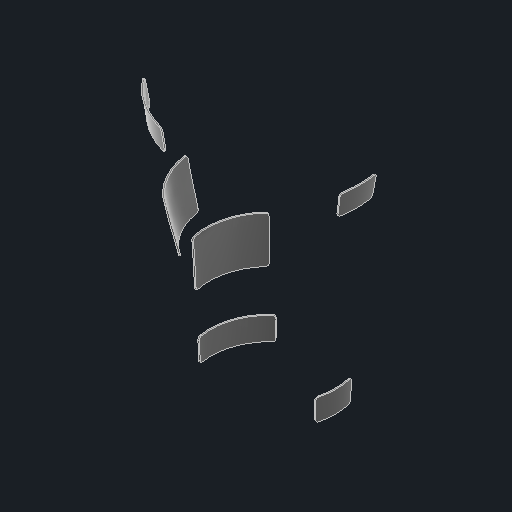
# Autodesk Inventor part: velcro
Saved by Autodesk Inventor 2026.2 (Build 302298010, 298A)
## iProperties
Created: 2026-04-16
Part Number: velcro
Material: Velcro Hook 88 / Loop 1000 (woven nylon, D12-4)
Document SubType Name: Modeling
Designer: user
Density: 0.109 g/cm^3
Appearance: Smooth - Black
Description: Copy of velcro, geometry unchanged. Material: Velcro Hook 88 / Loop 1000 - density from areal mass (TDS001-1), strength = dynamic shear 8.3 N/cm2, E/nu Nylon 6/6 (closest).
Mass: 2.13433 g
Surface Area: 280.537 cm^2
Volume: 19.581 cm^3
Author: user
Autodesk Inventor part; units mm, degrees
(part 1 of 2)
sketch "Sketch1" plane through (0, 0, 0) normal (0, 0, 1) x (1, 0, 0)
  line L0 (-180.6859, 44.2752) -> (-125.6859, 44.2752)
  arc A0 (-180.6859, 44.2752) -> (-180.6859, 21.2752) centre (-180.6859, 32.7752) ccw
  line L1 (-125.6859, 21.2752) -> (-180.6859, 21.2752)
  line L2 (-230.6859, -15.7248) -> (-125.6859, -15.7248)
  arc A1 (-230.6859, -15.7248) -> (-230.6859, -38.7248) centre (-230.6859, -27.2248) ccw
  line L3 (-125.6859, -38.7248) -> (-230.6859, -38.7248)
  line L4 (-125.6859, -38.7248) -> (-230.6859, -38.7248)
  arc A2 (-230.6859, -15.7248) -> (-230.6859, -38.7248) centre (-230.6859, -27.2248) ccw
  line L5 (-125.6859, -15.7248) -> (-125.6859, -38.7248)
  line L6 (-130.6859, 21.2752) -> (-180.6859, 21.2752)
  arc A3 (-180.6859, 44.2752) -> (-180.6859, 21.2752) centre (-180.6859, 32.7752) ccw
  line L7 (-242.1859, -27.2248) -> (-242.1859, 70.7547) construction
  line L8 (-125.6859, -27.2248) -> (-30.1859, -27.2248) construction
  line L9 (-30.1859, -27.2248) -> (-30.1859, 61.1167) construction
  line L10 (-15.419, 32.7752) -> (-30.1859, 32.7752) construction
  line L11 (-230.6859, -27.2248) -> (-230.6859, 28.0133) construction
  line L12 (-180.6859, 57.1317) -> (-180.6859, 8.4187) construction
  line L13 (-158.7098, 32.7752) -> (-202.6621, 32.7752) construction
  line L14 (-158.7098, 41.392) -> (-158.7098, 16.946) construction
  line L15 (-125.6859, 21.2752) -> (-125.6859, 44.2752)
  point P0 (0, 0)
  point P1 (-178.1859, -15.7248)
  dimension "d7" = 105
  dimension "d8" = 105
  dimension "d11" = 95.5
  dimension "d14" = 50
  dimension "d17" = 48.5
  constraints: 32 end point, 9 point on circle, 5 vertical, 4 centre point, 4 midpoint, 4 tangent, 3 horizontal, 3 point on line, 2 perpendicular, 1 coincident, 1 collinear
  measures "d7" distance of L2.start L5.start
  measures "d8" distance of L5.end L3.end
  measures "d11" distance of L8.start L8.end
  measures "d14" distance from line of L11 point (-180.686, 32.775)
  measures "d17" vertical distance of point (-178.186, -15.725) A0.centre
extrude "Extrusion1" [suppressed]
fillet "Fillet1" [suppressed]
ref_plane "Webbing_outer_face_X9.18" through (9.18, 0, 0) normal (1, 0, 0) x (0, 1, 0)
sketch "Velcro_v5" plane through (9.18, 0, 0) normal (1, 0, 0) x (0, 1, 0)
  line L0 (95.66, 344.45) -> (121.06, 344.45)
  line L1 (121.06, 344.45) -> (121.06, 416.45)
  line L2 (121.06, 416.45) -> (95.66, 416.45)
  line L3 (95.66, 416.45) -> (95.66, 344.45)
  line L4 (147.96, 340.5125) -> (198.76, 340.5125)
  line L5 (198.76, 340.5125) -> (198.76, 412.5125)
  line L6 (198.76, 412.5125) -> (147.96, 412.5125)
  line L7 (147.96, 412.5125) -> (147.96, 340.5125)
  line L8 (217.96, -556.485) -> (268.76, -556.485)
  line L9 (268.76, -556.485) -> (268.76, -484.485)
  line L10 (268.76, -484.485) -> (217.96, -484.485)
  line L11 (217.96, -484.485) -> (217.96, -556.485)
  line L12 (295.66, -604.3) -> (321.06, -604.3)
  line L13 (321.06, -604.3) -> (321.06, -532.3)
  line L14 (321.06, -532.3) -> (295.66, -532.3)
  line L15 (295.66, -532.3) -> (295.66, -604.3)
  line L16 (88.36, -60.14) -> (113.36, -60.14)
  line L17 (113.36, -60.14) -> (113.36, -20.14)
  line L18 (113.36, -20.14) -> (88.36, -20.14)
  line L19 (88.36, -20.14) -> (88.36, -60.14)
  line L20 (303.36, -60.14) -> (328.36, -60.14)
  line L21 (328.36, -60.14) -> (328.36, -20.14)
  line L22 (328.36, -20.14) -> (303.36, -20.14)
  line L23 (303.36, -20.14) -> (303.36, -60.14)
  constraints: 48 end point, 12 parallel, 6 horizontal, 6 perpendicular
extrude "Velcro_1.5mm" [suppressed]
ref_plane "Work Plane2" through (0, 0, 0) normal (0.7916281, 0, 0.6110032) x (0, 1, 0)
sketch "S7_vel_thigh_far" plane through (0, 0, 0) normal (0.7916281, 0, 0.6110032) x (0, 1, 0)
  spline S0 degree 4 poles (87.3, 89.6977) (87.4763, 89.7284) (87.829, 89.7897) (88.3579, 89.8816) (89.0633, 90.0041) (89.7686, 90.1263) (90.4739, 90.2483) (91.1793, 90.3702) (91.8847, 90.4919) (92.59, 90.6135) (93.2954, 90.7349) (94.0008, 90.8561) (94.7063, 90.9772) (95.4117, 91.0981) (96.1171, 91.2189) (96.8226, 91.3395) (97.528, 91.46) (98.2335, 91.5804) (98.939, 91.7006) (99.6445, 91.8207) (100.35, 91.9406) (101.0555, 92.0603) (101.7611, 92.1796) (102.4666, 92.2985) (103.1723, 92.4172) (103.8779, 92.5354) (104.5835, 92.6534) (105.2892, 92.7711) (105.9949, 92.8885) (106.7006, 93.0056) (107.4064, 93.1224) (108.1121, 93.2389) (108.8179, 93.3552) (109.5237, 93.4712) (110.2295, 93.5869) (110.9353, 93.7024) (111.6412, 93.8177) (112.1706, 93.904) (112.5235, 93.9614) (112.7, 93.9901) knots 0 0 0 0 0 0.027778 0.055556 0.083333 0.111111 0.138889 0.166667 0.194444 0.222222 0.25 0.277778 0.305556 0.333333 0.361111 0.388889 0.416667 0.444444 0.472222 0.5 0.527778 0.555556 0.583333 0.611111 0.638889 0.666667 0.694444 0.722222 0.75 0.777778 0.805556 0.833333 0.861111 0.888889 0.916667 0.944444 0.972222 1 1 1 1 1
  line L0 (112.7, 93.9901) -> (112.7, 95.4901)
  spline S1 degree 4 poles (112.7, 95.4901) (112.5235, 95.4614) (112.1706, 95.404) (111.6412, 95.3177) (110.9353, 95.2024) (110.2295, 95.0869) (109.5237, 94.9712) (108.8179, 94.8552) (108.1121, 94.7389) (107.4064, 94.6224) (106.7006, 94.5056) (105.9949, 94.3885) (105.2892, 94.2711) (104.5835, 94.1534) (103.8779, 94.0354) (103.1723, 93.9172) (102.4666, 93.7986) (101.7611, 93.6796) (101.0555, 93.5603) (100.35, 93.4406) (99.6445, 93.3207) (98.939, 93.2006) (98.2335, 93.0804) (97.528, 92.96) (96.8226, 92.8395) (96.1171, 92.7189) (95.4117, 92.5981) (94.7063, 92.4772) (94.0008, 92.3561) (93.2954, 92.2349) (92.59, 92.1135) (91.8847, 91.9919) (91.1793, 91.8702) (90.4739, 91.7483) (89.7686, 91.6263) (89.0633, 91.5041) (88.3579, 91.3816) (87.829, 91.2897) (87.4763, 91.2284) (87.3, 91.1977) knots 0 0 0 0 0 0.027778 0.055556 0.083333 0.111111 0.138889 0.166667 0.194444 0.222222 0.25 0.277778 0.305556 0.333333 0.361111 0.388889 0.416667 0.444444 0.472222 0.5 0.527778 0.555556 0.583333 0.611111 0.638889 0.666667 0.694444 0.722222 0.75 0.777778 0.805556 0.833333 0.861111 0.888889 0.916667 0.944444 0.972222 1 1 1 1 1
  line L1 (87.3, 91.1977) -> (87.3, 89.6977)
  line L2 (81.8572, 0) -> (118.1369, 0) projected
  point P0 (90.1222, 90.1875)
  point P1 (92.9444, 90.6745)
  point P2 (95.7667, 91.1589)
  point P3 (98.5889, 91.6409)
  point P4 (101.4111, 92.1204)
  point P5 (104.2333, 92.5948)
  point P6 (107.0556, 93.0643)
  point P7 (109.8778, 93.5292)
  point P8 (109.8778, 95.0292)
  point P9 (107.0556, 94.5643)
  point P10 (104.2333, 94.0948)
  point P11 (101.4111, 93.6204)
  point P12 (98.5889, 93.1409)
  point P13 (95.7667, 92.6589)
  point P14 (92.9444, 92.1745)
  point P15 (90.1222, 91.6875)
  constraints: 4 end point, 20 other
revolve "Velcro_closure_thigh_far" [suppressed]
ref_plane "Work Plane3" through (0, 0, 0) normal (0.5346339, 0, 0.8450838) x (0, 1, 0)
sketch "S7_vel_thigh_near" plane through (0, 0, 0) normal (0.5346339, 0, 0.8450838) x (0, 1, 0)
  spline S0 degree 4 poles (9.6, 73.5055) (9.7877, 73.538) (10.1629, 73.6035) (10.7256, 73.7037) (11.4755, 73.8411) (12.2251, 73.9824) (12.9744, 74.1274) (13.7233, 74.276) (14.472, 74.4282) (15.2203, 74.5837) (15.9683, 74.7423) (16.716, 74.9038) (17.4634, 75.0681) (18.2105, 75.2351) (18.9574, 75.4046) (19.704, 75.5765) (20.4504, 75.7507) (21.1966, 75.9269) (21.9425, 76.1051) (22.6883, 76.2851) (23.4338, 76.4668) (24.1792, 76.65) (24.9245, 76.8345) (25.6696, 77.0203) (26.4145, 77.2072) (27.1594, 77.395) (27.9042, 77.5836) (28.6488, 77.7729) (29.3935, 77.9627) (30.138, 78.1528) (30.8826, 78.3433) (31.6271, 78.5338) (32.3717, 78.7242) (33.1163, 78.9145) (33.8609, 79.1045) (34.6055, 79.294) (35.3503, 79.4829) (36.0951, 79.671) (36.84, 79.8583) (37.5851, 80.0444) (38.3302, 80.2295) (39.0756, 80.4132) (39.821, 80.5955) (40.5667, 80.7763) (41.3126, 80.9552) (42.0587, 81.1322) (42.805, 81.307) (43.5515, 81.4797) (44.2983, 81.6501) (45.0453, 81.8182) (45.7926, 81.9839) (46.5402, 82.1468) (47.2881, 82.3066) (48.0363, 82.463) (48.7848, 82.6158) (49.5337, 82.7654) (50.2827, 82.9126) (51.032, 83.0582) (51.7812, 83.203) (52.5305, 83.3477) (53.2799, 83.4923) (54.0292, 83.6367) (54.7785, 83.7806) (55.5279, 83.9241) (56.2774, 84.067) (57.0269, 84.2095) (57.7764, 84.3516) (58.526, 84.4933) (59.2756, 84.6348) (59.8378, 84.7407) (60.2126, 84.8112) (60.4, 84.8465) knots 0 0 0 0 0 0.014706 0.029412 0.044118 0.058824 0.073529 0.088235 0.102941 0.117647 0.132353 0.147059 0.161765 0.176471 0.191176 0.205882 0.220588 0.235294 0.25 0.264706 0.279412 0.294118 0.308824 0.323529 0.338235 0.352941 0.367647 0.382353 0.397059 0.411765 0.426471 0.441176 0.455882 0.470588 0.485294 0.5 0.514706 0.529412 0.544118 0.558824 0.573529 0.588235 0.602941 0.617647 0.632353 0.647059 0.661765 0.676471 0.691176 0.705882 0.720588 0.735294 0.75 0.764706 0.779412 0.794118 0.808824 0.823529 0.838235 0.852941 0.867647 0.882353 0.897059 0.911765 0.926471 0.941176 0.955882 0.970588 0.985294 1 1 1 1 1
  line L0 (60.4, 84.8465) -> (60.4, 86.3465)
  spline S1 degree 4 poles (60.4, 86.3465) (60.2126, 86.3112) (59.8378, 86.2407) (59.2756, 86.1348) (58.526, 85.9933) (57.7764, 85.8516) (57.0269, 85.7095) (56.2774, 85.567) (55.5279, 85.4241) (54.7785, 85.2806) (54.0292, 85.1367) (53.2799, 84.9923) (52.5305, 84.8477) (51.7812, 84.7031) (51.032, 84.5582) (50.2827, 84.4126) (49.5337, 84.2654) (48.7848, 84.1158) (48.0363, 83.963) (47.2881, 83.8066) (46.5402, 83.6468) (45.7926, 83.4839) (45.0453, 83.3182) (44.2983, 83.1501) (43.5515, 82.9797) (42.805, 82.807) (42.0587, 82.6322) (41.3126, 82.4552) (40.5667, 82.2763) (39.821, 82.0955) (39.0756, 81.9132) (38.3302, 81.7295) (37.5851, 81.5444) (36.84, 81.3583) (36.0951, 81.171) (35.3503, 80.9829) (34.6055, 80.794) (33.8609, 80.6045) (33.1163, 80.4145) (32.3717, 80.2242) (31.6271, 80.0338) (30.8826, 79.8433) (30.138, 79.6529) (29.3935, 79.4627) (28.6488, 79.2729) (27.9042, 79.0836) (27.1594, 78.895) (26.4145, 78.7072) (25.6696, 78.5203) (24.9245, 78.3345) (24.1792, 78.15) (23.4338, 77.9668) (22.6883, 77.7851) (21.9425, 77.6051) (21.1966, 77.4269) (20.4504, 77.2507) (19.704, 77.0765) (18.9574, 76.9046) (18.2105, 76.7351) (17.4634, 76.5681) (16.716, 76.4038) (15.9683, 76.2423) (15.2203, 76.0837) (14.472, 75.9282) (13.7233, 75.776) (12.9744, 75.6274) (12.2251, 75.4824) (11.4755, 75.3411) (10.7256, 75.2037) (10.1629, 75.1035) (9.7877, 75.038) (9.6, 75.0055) knots 0 0 0 0 0 0.014706 0.029412 0.044118 0.058824 0.073529 0.088235 0.102941 0.117647 0.132353 0.147059 0.161765 0.176471 0.191176 0.205882 0.220588 0.235294 0.25 0.264706 0.279412 0.294118 0.308824 0.323529 0.338235 0.352941 0.367647 0.382353 0.397059 0.411765 0.426471 0.441176 0.455882 0.470588 0.485294 0.5 0.514706 0.529412 0.544118 0.558824 0.573529 0.588235 0.602941 0.617647 0.632353 0.647059 0.661765 0.676471 0.691176 0.705882 0.720588 0.735294 0.75 0.764706 0.779412 0.794118 0.808824 0.823529 0.838235 0.852941 0.867647 0.882353 0.897059 0.911765 0.926471 0.941176 0.955882 0.970588 0.985294 1 1 1 1 1
  line L1 (9.6, 75.0055) -> (9.6, 73.5055)
  line L2 (-1.3086, 0) -> (71.2778, 0) projected
  point P0 (12.5882, 74.0529)
  point P1 (15.5765, 74.6595)
  point P2 (18.5647, 75.3157)
  point P3 (21.5529, 76.0122)
  point P4 (24.5412, 76.7397)
  point P5 (27.5294, 77.4888)
  point P6 (30.5176, 78.2499)
  point P7 (33.5059, 79.0139)
  point P8 (36.4941, 79.7712)
  point P9 (39.4824, 80.5126)
  point P10 (42.4706, 81.2285)
  point P11 (45.4588, 81.9096)
  point P12 (48.4471, 82.5466)
  point P13 (51.4353, 83.1361)
  point P14 (54.4235, 83.7124)
  point P15 (57.4118, 84.2824)
  point P16 (57.4118, 85.7824)
  point P17 (54.4235, 85.2124)
  point P18 (51.4353, 84.6361)
  point P19 (48.4471, 84.0466)
  point P20 (45.4588, 83.4096)
  point P21 (42.4706, 82.7285)
  point P22 (39.4824, 82.0126)
  point P23 (36.4941, 81.2712)
  point P24 (33.5059, 80.5139)
  point P25 (30.5176, 79.7499)
  point P26 (27.5294, 78.9888)
  point P27 (24.5412, 78.2397)
  point P28 (21.5529, 77.5122)
  point P29 (18.5647, 76.8157)
  point P30 (15.5765, 76.1595)
  point P31 (12.5882, 75.5529)
  constraints: 4 end point, 36 other
revolve "Velcro_closure_thigh_near" [suppressed]
ref_plane "Work Plane4" through (0, 0, 0) normal (-0.2561526, 0, 0.9666364) x (0, 1, 0)
sketch "S7_vel_shank_near" plane through (0, 0, 0) normal (-0.2561526, 0, 0.9666364) x (0, 1, 0)
  spline S0 degree 4 poles (-60.4, 68.8155) (-60.2132, 68.8227) (-59.8395, 68.8372) (-59.279, 68.859) (-58.5317, 68.8882) (-57.7844, 68.9177) (-57.0371, 68.9474) (-56.2898, 68.9773) (-55.5426, 69.0075) (-54.7953, 69.0379) (-54.048, 69.0686) (-53.3007, 69.0995) (-52.5535, 69.1307) (-51.8062, 69.1621) (-51.0589, 69.1938) (-50.3117, 69.2258) (-49.5644, 69.258) (-48.8172, 69.2906) (-48.07, 69.3234) (-47.3227, 69.3565) (-46.5755, 69.3899) (-45.8283, 69.4236) (-45.0811, 69.4576) (-44.3339, 69.4919) (-43.5867, 69.5265) (-42.8395, 69.5615) (-42.0923, 69.5967) (-41.3452, 69.6323) (-40.598, 69.6682) (-39.8508, 69.7045) (-39.1037, 69.7411) (-38.3565, 69.7781) (-37.6094, 69.8154) (-36.8623, 69.8531) (-36.1152, 69.8911) (-35.3681, 69.9295) (-34.621, 69.9682) (-33.8739, 70.0074) (-33.1268, 70.0469) (-32.3797, 70.0868) (-31.6327, 70.1271) (-30.8856, 70.1678) (-30.1386, 70.2089) (-29.3915, 70.2504) (-28.6445, 70.2923) (-27.8975, 70.3346) (-27.1505, 70.3774) (-26.4035, 70.4205) (-25.6566, 70.4641) (-24.9096, 70.5081) (-24.1626, 70.5526) (-23.4157, 70.5975) (-22.6688, 70.6429) (-21.9219, 70.6887) (-21.175, 70.7349) (-20.4281, 70.7817) (-19.6812, 70.8289) (-18.9344, 70.8765) (-18.1875, 70.9247) (-17.4407, 70.9733) (-16.6939, 71.0224) (-15.9471, 71.072) (-15.2003, 71.1221) (-14.4536, 71.1727) (-13.7068, 71.2237) (-12.9601, 71.2754) (-12.2134, 71.3275) (-11.4667, 71.3801) (-10.72, 71.4333) (-10.16, 71.4735) (-9.7867, 71.5006) (-9.6, 71.5141) knots 0 0 0 0 0 0.014706 0.029412 0.044118 0.058824 0.073529 0.088235 0.102941 0.117647 0.132353 0.147059 0.161765 0.176471 0.191176 0.205882 0.220588 0.235294 0.25 0.264706 0.279412 0.294118 0.308824 0.323529 0.338235 0.352941 0.367647 0.382353 0.397059 0.411765 0.426471 0.441176 0.455882 0.470588 0.485294 0.5 0.514706 0.529412 0.544118 0.558824 0.573529 0.588235 0.602941 0.617647 0.632353 0.647059 0.661765 0.676471 0.691176 0.705882 0.720588 0.735294 0.75 0.764706 0.779412 0.794118 0.808824 0.823529 0.838235 0.852941 0.867647 0.882353 0.897059 0.911765 0.926471 0.941176 0.955882 0.970588 0.985294 1 1 1 1 1
  line L0 (-9.6, 71.5141) -> (-9.6, 73.0141)
  spline S1 degree 4 poles (-9.6, 73.0141) (-9.7867, 73.0006) (-10.16, 72.9735) (-10.72, 72.9333) (-11.4667, 72.8801) (-12.2134, 72.8275) (-12.9601, 72.7754) (-13.7068, 72.7237) (-14.4536, 72.6727) (-15.2003, 72.6221) (-15.9471, 72.572) (-16.6939, 72.5224) (-17.4407, 72.4733) (-18.1875, 72.4247) (-18.9344, 72.3765) (-19.6812, 72.3289) (-20.4281, 72.2817) (-21.175, 72.2349) (-21.9219, 72.1887) (-22.6688, 72.1429) (-23.4157, 72.0975) (-24.1626, 72.0526) (-24.9096, 72.0081) (-25.6566, 71.9641) (-26.4035, 71.9205) (-27.1505, 71.8774) (-27.8975, 71.8346) (-28.6445, 71.7923) (-29.3915, 71.7504) (-30.1386, 71.7089) (-30.8856, 71.6678) (-31.6327, 71.6271) (-32.3797, 71.5868) (-33.1268, 71.5469) (-33.8739, 71.5074) (-34.621, 71.4682) (-35.3681, 71.4295) (-36.1152, 71.3911) (-36.8623, 71.3531) (-37.6094, 71.3154) (-38.3565, 71.2781) (-39.1037, 71.2411) (-39.8508, 71.2045) (-40.598, 71.1682) (-41.3452, 71.1323) (-42.0923, 71.0967) (-42.8395, 71.0615) (-43.5867, 71.0265) (-44.3339, 70.9919) (-45.0811, 70.9576) (-45.8283, 70.9236) (-46.5755, 70.8899) (-47.3227, 70.8565) (-48.07, 70.8234) (-48.8172, 70.7906) (-49.5644, 70.758) (-50.3117, 70.7258) (-51.0589, 70.6938) (-51.8062, 70.6621) (-52.5535, 70.6307) (-53.3007, 70.5995) (-54.048, 70.5686) (-54.7953, 70.5379) (-55.5426, 70.5075) (-56.2898, 70.4773) (-57.0371, 70.4474) (-57.7844, 70.4177) (-58.5317, 70.3882) (-59.279, 70.359) (-59.8395, 70.3372) (-60.2132, 70.3227) (-60.4, 70.3155) knots 0 0 0 0 0 0.014706 0.029412 0.044118 0.058824 0.073529 0.088235 0.102941 0.117647 0.132353 0.147059 0.161765 0.176471 0.191176 0.205882 0.220588 0.235294 0.25 0.264706 0.279412 0.294118 0.308824 0.323529 0.338235 0.352941 0.367647 0.382353 0.397059 0.411765 0.426471 0.441176 0.455882 0.470588 0.485294 0.5 0.514706 0.529412 0.544118 0.558824 0.573529 0.588235 0.602941 0.617647 0.632353 0.647059 0.661765 0.676471 0.691176 0.705882 0.720588 0.735294 0.75 0.764706 0.779412 0.794118 0.808824 0.823529 0.838235 0.852941 0.867647 0.882353 0.897059 0.911765 0.926471 0.941176 0.955882 0.970588 0.985294 1 1 1 1 1
  line L1 (-60.4, 70.3155) -> (-60.4, 68.8155)
  line L2 (-71.2749, 0) -> (1.2865, 0) projected
  point P0 (-57.4118, 68.9325)
  point P1 (-54.4235, 69.0532)
  point P2 (-51.4353, 69.1779)
  point P3 (-48.4471, 69.3068)
  point P4 (-45.4588, 69.4404)
  point P5 (-42.4706, 69.5789)
  point P6 (-39.4824, 69.7226)
  point P7 (-36.4941, 69.8718)
  point P8 (-33.5059, 70.0269)
  point P9 (-30.5176, 70.1881)
  point P10 (-27.5294, 70.3557)
  point P11 (-24.5412, 70.5301)
  point P12 (-21.5529, 70.7116)
  point P13 (-18.5647, 70.9004)
  point P14 (-15.5765, 71.0969)
  point P15 (-12.5882, 71.3014)
  point P16 (-12.5882, 72.8014)
  point P17 (-15.5765, 72.5969)
  point P18 (-18.5647, 72.4004)
  point P19 (-21.5529, 72.2116)
  point P20 (-24.5412, 72.0301)
  point P21 (-27.5294, 71.8557)
  point P22 (-30.5176, 71.6881)
  point P23 (-33.5059, 71.5269)
  point P24 (-36.4941, 71.3718)
  point P25 (-39.4824, 71.2226)
  point P26 (-42.4706, 71.0789)
  point P27 (-45.4588, 70.9404)
  point P28 (-48.4471, 70.8068)
  point P29 (-51.4353, 70.6779)
  point P30 (-54.4235, 70.5532)
  point P31 (-57.4118, 70.4325)
  constraints: 4 end point, 36 other
revolve "Velcro_closure_shank_near" [suppressed]
ref_plane "Work Plane5" through (0, 0, 0) normal (-0.3395989, 0, 0.9405703) x (0, 1, 0)
sketch "S7_vel_shank_far" plane through (0, 0, 0) normal (-0.3395989, 0, 0.9405703) x (0, 1, 0)
  spline S0 degree 4 poles (-112.7, 67.0412) (-112.5236, 67.0472) (-112.1708, 67.0594) (-111.6417, 67.0776) (-110.9361, 67.1017) (-110.2306, 67.1258) (-109.5251, 67.1497) (-108.8195, 67.1736) (-108.114, 67.1974) (-107.4084, 67.221) (-106.7029, 67.2446) (-105.9973, 67.2682) (-105.2918, 67.2916) (-104.5862, 67.315) (-103.8807, 67.3383) (-103.1751, 67.3616) (-102.4695, 67.3848) (-101.764, 67.4079) (-101.0584, 67.431) (-100.3529, 67.4541) (-99.6473, 67.4771) (-98.9418, 67.5001) (-98.2362, 67.523) (-97.5306, 67.5459) (-96.8251, 67.5688) (-96.1195, 67.5917) (-95.414, 67.6145) (-94.7084, 67.6374) (-94.0028, 67.6602) (-93.2973, 67.683) (-92.5917, 67.7059) (-91.8861, 67.7287) (-91.1806, 67.7515) (-90.475, 67.7744) (-89.7695, 67.7973) (-89.0639, 67.8201) (-88.3583, 67.8431) (-87.8292, 67.8603) (-87.4764, 67.8717) (-87.3, 67.8775) knots 0 0 0 0 0 0.027778 0.055556 0.083333 0.111111 0.138889 0.166667 0.194444 0.222222 0.25 0.277778 0.305556 0.333333 0.361111 0.388889 0.416667 0.444444 0.472222 0.5 0.527778 0.555556 0.583333 0.611111 0.638889 0.666667 0.694444 0.722222 0.75 0.777778 0.805556 0.833333 0.861111 0.888889 0.916667 0.944444 0.972222 1 1 1 1 1
  line L0 (-87.3, 67.8775) -> (-87.3, 69.3775)
  spline S1 degree 4 poles (-87.3, 69.3775) (-87.4764, 69.3717) (-87.8292, 69.3603) (-88.3583, 69.3431) (-89.0639, 69.3201) (-89.7695, 69.2973) (-90.475, 69.2744) (-91.1806, 69.2515) (-91.8861, 69.2287) (-92.5917, 69.2059) (-93.2973, 69.183) (-94.0028, 69.1602) (-94.7084, 69.1374) (-95.414, 69.1145) (-96.1195, 69.0917) (-96.8251, 69.0688) (-97.5306, 69.0459) (-98.2362, 69.023) (-98.9418, 69.0001) (-99.6473, 68.9771) (-100.3529, 68.9541) (-101.0584, 68.931) (-101.764, 68.9079) (-102.4695, 68.8848) (-103.1751, 68.8616) (-103.8807, 68.8383) (-104.5862, 68.815) (-105.2918, 68.7916) (-105.9973, 68.7682) (-106.7029, 68.7446) (-107.4084, 68.721) (-108.114, 68.6974) (-108.8195, 68.6736) (-109.5251, 68.6497) (-110.2306, 68.6258) (-110.9361, 68.6017) (-111.6417, 68.5776) (-112.1708, 68.5594) (-112.5236, 68.5472) (-112.7, 68.5412) knots 0 0 0 0 0 0.027778 0.055556 0.083333 0.111111 0.138889 0.166667 0.194444 0.222222 0.25 0.277778 0.305556 0.333333 0.361111 0.388889 0.416667 0.444444 0.472222 0.5 0.527778 0.555556 0.583333 0.611111 0.638889 0.666667 0.694444 0.722222 0.75 0.777778 0.805556 0.833333 0.861111 0.888889 0.916667 0.944444 0.972222 1 1 1 1 1
  line L1 (-112.7, 68.5412) -> (-112.7, 67.0412)
  line L2 (-118.1359, 0) -> (-81.8643, 0) projected
  point P0 (-109.8778, 67.1378)
  point P1 (-107.0556, 67.2328)
  point P2 (-104.2333, 67.3267)
  point P3 (-101.4111, 67.4195)
  point P4 (-98.5889, 67.5115)
  point P5 (-95.7667, 67.6031)
  point P6 (-92.9444, 67.6944)
  point P7 (-90.1222, 67.7858)
  point P8 (-90.1222, 69.2858)
  point P9 (-92.9444, 69.1944)
  point P10 (-95.7667, 69.1031)
  point P11 (-98.5889, 69.0115)
  point P12 (-101.4111, 68.9195)
  point P13 (-104.2333, 68.8267)
  point P14 (-107.0556, 68.7328)
  point P15 (-109.8778, 68.6378)
  constraints: 4 end point, 20 other
revolve "Velcro_closure_shank_far" [suppressed]
ref_plane "Work Plane6" through (0, 0, 0) normal (0, 0, -1) x (0, 1, 0)
sketch "S7_m3_1" plane through (0, 0, 0) normal (0, 0, -1) x (0, 1, 0)
  spline S0 degree 4 poles (95, 97.0075) (95.1562, 97.0343) (95.4686, 97.0878) (95.9371, 97.168) (96.5619, 97.2749) (97.1866, 97.3817) (97.8114, 97.4884) (98.4361, 97.595) (99.0609, 97.7014) (99.6857, 97.8078) (100.3105, 97.9139) (100.9353, 98.0198) (101.5602, 98.1256) (102.185, 98.231) (102.8099, 98.3363) (103.4348, 98.4412) (104.0597, 98.5459) (104.6846, 98.6503) (105.3096, 98.7545) (105.9345, 98.8584) (106.5595, 98.9622) (107.1845, 99.0657) (107.8095, 99.169) (108.4346, 99.2721) (109.0596, 99.3749) (109.6847, 99.4776) (110.3098, 99.5801) (110.9348, 99.6823) (111.5599, 99.7844) (112.1851, 99.8863) (112.8102, 99.9881) (113.4353, 100.0896) (114.0605, 100.191) (114.6857, 100.2922) (115.3108, 100.3932) (115.936, 100.4941) (116.5612, 100.5949) (117.1864, 100.6955) (117.8117, 100.796) (118.4369, 100.8963) (119.0621, 100.9965) (119.5311, 101.0716) (119.8437, 101.1216) (120, 101.1466) knots 0 0 0 0 0 0.025 0.05 0.075 0.1 0.125 0.15 0.175 0.2 0.225 0.25 0.275 0.3 0.325 0.35 0.375 0.4 0.425 0.45 0.475 0.5 0.525 0.55 0.575 0.6 0.625 0.65 0.675 0.7 0.725 0.75 0.775 0.8 0.825 0.85 0.875 0.9 0.925 0.95 0.975 1 1 1 1 1
  line L0 (120, 101.1466) -> (120, 102.6466)
  spline S1 degree 4 poles (120, 102.6466) (119.8437, 102.6216) (119.5311, 102.5716) (119.0621, 102.4965) (118.4369, 102.3963) (117.8117, 102.296) (117.1864, 102.1955) (116.5612, 102.0949) (115.936, 101.9941) (115.3108, 101.8932) (114.6857, 101.7922) (114.0605, 101.691) (113.4353, 101.5896) (112.8102, 101.4881) (112.1851, 101.3863) (111.5599, 101.2844) (110.9348, 101.1823) (110.3098, 101.0801) (109.6847, 100.9776) (109.0596, 100.8749) (108.4346, 100.7721) (107.8095, 100.669) (107.1845, 100.5657) (106.5595, 100.4622) (105.9345, 100.3584) (105.3096, 100.2545) (104.6846, 100.1503) (104.0597, 100.0459) (103.4348, 99.9412) (102.8099, 99.8363) (102.185, 99.7311) (101.5602, 99.6256) (100.9353, 99.5199) (100.3105, 99.4139) (99.6857, 99.3078) (99.0609, 99.2014) (98.4361, 99.095) (97.8114, 98.9884) (97.1866, 98.8817) (96.5619, 98.7749) (95.9371, 98.668) (95.4686, 98.5878) (95.1562, 98.5343) (95, 98.5075) knots 0 0 0 0 0 0.025 0.05 0.075 0.1 0.125 0.15 0.175 0.2 0.225 0.25 0.275 0.3 0.325 0.35 0.375 0.4 0.425 0.45 0.475 0.5 0.525 0.55 0.575 0.6 0.625 0.65 0.675 0.7 0.725 0.75 0.775 0.8 0.825 0.85 0.875 0.9 0.925 0.95 0.975 1 1 1 1 1
  line L1 (95, 98.5075) -> (95, 97.0075)
  line L2 (89.6416, 0) -> (125.3517, 0) projected
  point P0 (97.5, 97.4352)
  point P1 (100, 97.8611)
  point P2 (102.5, 98.2841)
  point P3 (105, 98.7028)
  point P4 (107.5, 99.1178)
  point P5 (110, 99.5293)
  point P6 (112.5, 99.9376)
  point P7 (115, 100.343)
  point P8 (117.5, 100.7459)
  point P9 (117.5, 102.2459)
  point P10 (115, 101.843)
  point P11 (112.5, 101.4376)
  point P12 (110, 101.0293)
  point P13 (107.5, 100.6178)
  point P14 (105, 100.2028)
  point P15 (102.5, 99.7841)
  point P16 (100, 99.3611)
  point P17 (97.5, 98.9352)
  constraints: 4 end point, 22 other
revolve "M3_patch_thigh" [suppressed]
ref_plane "Work Plane7" through (0, 0, 0) normal (0, 0, -1) x (0, 1, 0)
sketch "S7_m3_-1" plane through (0, 0, 0) normal (0, 0, -1) x (0, 1, 0)
  spline S0 degree 4 poles (-120, 72.7624) (-119.8438, 72.7681) (-119.5313, 72.7795) (-119.0625, 72.7965) (-118.4376, 72.819) (-117.8126, 72.8415) (-117.1876, 72.8638) (-116.5626, 72.886) (-115.9376, 72.9082) (-115.3126, 72.9302) (-114.6877, 72.9521) (-114.0627, 72.9739) (-113.4377, 72.9956) (-112.8127, 73.0173) (-112.1877, 73.0388) (-111.5627, 73.0603) (-110.9377, 73.0817) (-110.3127, 73.103) (-109.6877, 73.1242) (-109.0627, 73.1454) (-108.4377, 73.1665) (-107.8127, 73.1875) (-107.1877, 73.2084) (-106.5627, 73.2293) (-105.9377, 73.2501) (-105.3127, 73.2709) (-104.6877, 73.2916) (-104.0627, 73.3123) (-103.4377, 73.3329) (-102.8126, 73.3535) (-102.1876, 73.374) (-101.5626, 73.3945) (-100.9376, 73.415) (-100.3126, 73.4354) (-99.6876, 73.4558) (-99.0626, 73.4761) (-98.4376, 73.4964) (-97.8126, 73.5168) (-97.1875, 73.537) (-96.5625, 73.5573) (-95.9375, 73.5776) (-95.4688, 73.5928) (-95.1563, 73.6029) (-95, 73.6079) knots 0 0 0 0 0 0.025 0.05 0.075 0.1 0.125 0.15 0.175 0.2 0.225 0.25 0.275 0.3 0.325 0.35 0.375 0.4 0.425 0.45 0.475 0.5 0.525 0.55 0.575 0.6 0.625 0.65 0.675 0.7 0.725 0.75 0.775 0.8 0.825 0.85 0.875 0.9 0.925 0.95 0.975 1 1 1 1 1
  line L0 (-95, 73.6079) -> (-95, 75.1079)
  spline S1 degree 4 poles (-95, 75.1079) (-95.1563, 75.1029) (-95.4688, 75.0928) (-95.9375, 75.0776) (-96.5625, 75.0573) (-97.1875, 75.037) (-97.8126, 75.0168) (-98.4376, 74.9964) (-99.0626, 74.9761) (-99.6876, 74.9558) (-100.3126, 74.9354) (-100.9376, 74.915) (-101.5626, 74.8945) (-102.1876, 74.874) (-102.8126, 74.8535) (-103.4377, 74.8329) (-104.0627, 74.8123) (-104.6877, 74.7916) (-105.3127, 74.7709) (-105.9377, 74.7501) (-106.5627, 74.7293) (-107.1877, 74.7084) (-107.8127, 74.6875) (-108.4377, 74.6665) (-109.0627, 74.6454) (-109.6877, 74.6242) (-110.3127, 74.603) (-110.9377, 74.5817) (-111.5627, 74.5603) (-112.1877, 74.5388) (-112.8127, 74.5173) (-113.4377, 74.4956) (-114.0627, 74.4739) (-114.6877, 74.4521) (-115.3126, 74.4302) (-115.9376, 74.4082) (-116.5626, 74.386) (-117.1876, 74.3638) (-117.8126, 74.3415) (-118.4376, 74.319) (-119.0625, 74.2965) (-119.5313, 74.2795) (-119.8438, 74.2681) (-120, 74.2624) knots 0 0 0 0 0 0.025 0.05 0.075 0.1 0.125 0.15 0.175 0.2 0.225 0.25 0.275 0.3 0.325 0.35 0.375 0.4 0.425 0.45 0.475 0.5 0.525 0.55 0.575 0.6 0.625 0.65 0.675 0.7 0.725 0.75 0.775 0.8 0.825 0.85 0.875 0.9 0.925 0.95 0.975 1 1 1 1 1
  line L1 (-120, 74.2624) -> (-120, 72.7624)
  line L2 (-125.3506, 0) -> (-89.6498, 0) projected
  point P0 (-117.5, 72.8526)
  point P1 (-115, 72.9411)
  point P2 (-112.5, 73.0281)
  point P3 (-110, 73.1136)
  point P4 (-107.5, 73.198)
  point P5 (-105, 73.2813)
  point P6 (-102.5, 73.3638)
  point P7 (-100, 73.4456)
  point P8 (-97.5, 73.5269)
  point P9 (-97.5, 75.0269)
  point P10 (-100, 74.9456)
  point P11 (-102.5, 74.8638)
  point P12 (-105, 74.7813)
  point P13 (-107.5, 74.698)
  point P14 (-110, 74.6136)
  point P15 (-112.5, 74.5281)
  point P16 (-115, 74.4411)
  point P17 (-117.5, 74.3526)
  constraints: 4 end point, 22 other
revolve "M3_patch_shank" [suppressed]
feature "Velcro_v7" [suppressed]
fillet "Corners_R3" [suppressed]
ref_plane "Work Plane8" through (0, 0, 0) normal (0.8299959, 0, 0.5577695) x (0, 1, 0)
sketch "S8_vel_thigh_far" plane through (0, 0, 0) normal (0.8299959, 0, 0.5577695) x (0, 1, 0)
  spline S0 degree 4 poles (137.3, 97.9046) (137.4764, 97.9324) (137.8292, 97.988) (138.3584, 98.0715) (139.0641, 98.1828) (139.7697, 98.2942) (140.4753, 98.4057) (141.1809, 98.5171) (141.8865, 98.6287) (142.5921, 98.7403) (143.2977, 98.852) (144.0033, 98.9638) (144.7089, 99.0757) (145.4145, 99.1877) (146.12, 99.2998) (146.8256, 99.412) (147.5312, 99.5243) (148.2367, 99.6367) (148.9422, 99.7494) (149.6478, 99.8621) (150.3533, 99.975) (151.0588, 100.0878) (151.7643, 100.2007) (152.4698, 100.3135) (153.1753, 100.4263) (153.8809, 100.5391) (154.5864, 100.6518) (155.2919, 100.7645) (155.9974, 100.8772) (156.703, 100.9899) (157.4085, 101.1026) (158.114, 101.2152) (158.8195, 101.3278) (159.5251, 101.4404) (160.2306, 101.553) (160.9362, 101.6656) (161.6417, 101.7781) (162.1708, 101.8625) (162.5236, 101.9187) (162.7, 101.9469) knots 0 0 0 0 0 0.027778 0.055556 0.083333 0.111111 0.138889 0.166667 0.194444 0.222222 0.25 0.277778 0.305556 0.333333 0.361111 0.388889 0.416667 0.444444 0.472222 0.5 0.527778 0.555556 0.583333 0.611111 0.638889 0.666667 0.694444 0.722222 0.75 0.777778 0.805556 0.833333 0.861111 0.888889 0.916667 0.944444 0.972222 1 1 1 1 1
  line L0 (162.7, 101.9469) -> (162.7, 103.4469)
  spline S1 degree 4 poles (162.7, 103.4469) (162.5236, 103.4187) (162.1708, 103.3625) (161.6417, 103.2781) (160.9362, 103.1656) (160.2306, 103.053) (159.5251, 102.9404) (158.8195, 102.8278) (158.114, 102.7152) (157.4085, 102.6026) (156.703, 102.4899) (155.9974, 102.3772) (155.2919, 102.2645) (154.5864, 102.1518) (153.8809, 102.0391) (153.1753, 101.9263) (152.4698, 101.8135) (151.7643, 101.7007) (151.0588, 101.5878) (150.3533, 101.475) (149.6478, 101.3621) (148.9422, 101.2494) (148.2367, 101.1367) (147.5312, 101.0243) (146.8256, 100.912) (146.12, 100.7998) (145.4145, 100.6877) (144.7089, 100.5757) (144.0033, 100.4638) (143.2977, 100.352) (142.5921, 100.2403) (141.8865, 100.1287) (141.1809, 100.0171) (140.4753, 99.9057) (139.7697, 99.7942) (139.0641, 99.6828) (138.3584, 99.5715) (137.8292, 99.488) (137.4764, 99.4324) (137.3, 99.4046) knots 0 0 0 0 0 0.027778 0.055556 0.083333 0.111111 0.138889 0.166667 0.194444 0.222222 0.25 0.277778 0.305556 0.333333 0.361111 0.388889 0.416667 0.444444 0.472222 0.5 0.527778 0.555556 0.583333 0.611111 0.638889 0.666667 0.694444 0.722222 0.75 0.777778 0.805556 0.833333 0.861111 0.888889 0.916667 0.944444 0.972222 1 1 1 1 1
  line L1 (137.3, 99.4046) -> (137.3, 97.9046)
  line L2 (131.8642, 0) -> (168.1369, 0) projected
  point P0 (140.1222, 98.3499)
  point P1 (142.9444, 98.7961)
  point P2 (145.7667, 99.2436)
  point P3 (148.5889, 99.693)
  point P4 (151.4111, 100.1442)
  point P5 (154.2333, 100.5954)
  point P6 (157.0556, 101.0462)
  point P7 (159.8778, 101.4967)
  point P8 (159.8778, 102.9967)
  point P9 (157.0556, 102.5462)
  point P10 (154.2333, 102.0954)
  point P11 (151.4111, 101.6442)
  point P12 (148.5889, 101.193)
  point P13 (145.7667, 100.7436)
  point P14 (142.9444, 100.2961)
  point P15 (140.1222, 99.8499)
  constraints: 4 end point, 20 other
revolve "Velcro_closure_thigh_far_v8" add sketch "S8_vel_thigh_far" angle 41.295 mid plane about axis through (0, -10, 0) along (0, 1, 0) separate body
ref_plane "Work Plane9" through (0, 0, 0) normal (0.5346339, 0, 0.8450838) x (0, 1, 0)
sketch "S8_vel_thigh_near" plane through (0, 0, 0) normal (0.5346339, 0, 0.8450838) x (0, 1, 0)
  spline S0 degree 4 poles (9.6, 73.5055) (9.7877, 73.538) (10.1629, 73.6035) (10.7256, 73.7037) (11.4755, 73.8411) (12.2251, 73.9824) (12.9744, 74.1274) (13.7233, 74.276) (14.472, 74.4282) (15.2203, 74.5837) (15.9683, 74.7423) (16.716, 74.9038) (17.4634, 75.0681) (18.2105, 75.2351) (18.9574, 75.4046) (19.704, 75.5765) (20.4504, 75.7507) (21.1966, 75.9269) (21.9425, 76.1051) (22.6883, 76.2851) (23.4338, 76.4668) (24.1792, 76.65) (24.9245, 76.8345) (25.6696, 77.0203) (26.4145, 77.2072) (27.1594, 77.395) (27.9042, 77.5836) (28.6488, 77.7729) (29.3935, 77.9627) (30.138, 78.1528) (30.8826, 78.3433) (31.6271, 78.5338) (32.3717, 78.7242) (33.1163, 78.9145) (33.8609, 79.1045) (34.6055, 79.294) (35.3503, 79.4829) (36.0951, 79.671) (36.84, 79.8583) (37.5851, 80.0444) (38.3302, 80.2295) (39.0756, 80.4132) (39.821, 80.5955) (40.5667, 80.7763) (41.3126, 80.9552) (42.0587, 81.1322) (42.805, 81.307) (43.5515, 81.4797) (44.2983, 81.6501) (45.0453, 81.8182) (45.7926, 81.9839) (46.5402, 82.1468) (47.2881, 82.3066) (48.0363, 82.463) (48.7848, 82.6158) (49.5337, 82.7654) (50.2827, 82.9126) (51.032, 83.0582) (51.7812, 83.2031) (52.5305, 83.3477) (53.2799, 83.4923) (54.0292, 83.6367) (54.7785, 83.7806) (55.5279, 83.9241) (56.2774, 84.067) (57.0269, 84.2095) (57.7764, 84.3516) (58.526, 84.4933) (59.2756, 84.6348) (59.8378, 84.7407) (60.2126, 84.8112) (60.4, 84.8465) knots 0 0 0 0 0 0.014706 0.029412 0.044118 0.058824 0.073529 0.088235 0.102941 0.117647 0.132353 0.147059 0.161765 0.176471 0.191176 0.205882 0.220588 0.235294 0.25 0.264706 0.279412 0.294118 0.308824 0.323529 0.338235 0.352941 0.367647 0.382353 0.397059 0.411765 0.426471 0.441176 0.455882 0.470588 0.485294 0.5 0.514706 0.529412 0.544118 0.558824 0.573529 0.588235 0.602941 0.617647 0.632353 0.647059 0.661765 0.676471 0.691176 0.705882 0.720588 0.735294 0.75 0.764706 0.779412 0.794118 0.808824 0.823529 0.838235 0.852941 0.867647 0.882353 0.897059 0.911765 0.926471 0.941176 0.955882 0.970588 0.985294 1 1 1 1 1
  line L0 (60.4, 84.8465) -> (60.4, 86.3465)
  spline S1 degree 4 poles (60.4, 86.3465) (60.2126, 86.3112) (59.8378, 86.2407) (59.2756, 86.1348) (58.526, 85.9933) (57.7764, 85.8516) (57.0269, 85.7095) (56.2774, 85.567) (55.5279, 85.4241) (54.7785, 85.2807) (54.0292, 85.1367) (53.2799, 84.9923) (52.5305, 84.8477) (51.7812, 84.7031) (51.032, 84.5582) (50.2827, 84.4126) (49.5337, 84.2654) (48.7848, 84.1158) (48.0363, 83.963) (47.2881, 83.8066) (46.5402, 83.6468) (45.7926, 83.4839) (45.0453, 83.3182) (44.2983, 83.1501) (43.5515, 82.9797) (42.805, 82.807) (42.0587, 82.6322) (41.3126, 82.4552) (40.5667, 82.2763) (39.821, 82.0955) (39.0756, 81.9132) (38.3302, 81.7295) (37.5851, 81.5444) (36.84, 81.3583) (36.0951, 81.171) (35.3503, 80.9829) (34.6055, 80.794) (33.8609, 80.6045) (33.1163, 80.4145) (32.3717, 80.2242) (31.6271, 80.0338) (30.8826, 79.8433) (30.138, 79.6529) (29.3935, 79.4627) (28.6488, 79.2729) (27.9042, 79.0836) (27.1594, 78.895) (26.4145, 78.7072) (25.6696, 78.5203) (24.9245, 78.3345) (24.1792, 78.15) (23.4338, 77.9668) (22.6883, 77.7851) (21.9425, 77.6051) (21.1966, 77.4269) (20.4504, 77.2507) (19.704, 77.0765) (18.9574, 76.9046) (18.2105, 76.7351) (17.4634, 76.5681) (16.716, 76.4038) (15.9683, 76.2423) (15.2203, 76.0837) (14.472, 75.9282) (13.7233, 75.776) (12.9744, 75.6274) (12.2251, 75.4823) (11.4755, 75.3411) (10.7256, 75.2037) (10.1629, 75.1035) (9.7877, 75.038) (9.6, 75.0055) knots 0 0 0 0 0 0.014706 0.029412 0.044118 0.058824 0.073529 0.088235 0.102941 0.117647 0.132353 0.147059 0.161765 0.176471 0.191176 0.205882 0.220588 0.235294 0.25 0.264706 0.279412 0.294118 0.308824 0.323529 0.338235 0.352941 0.367647 0.382353 0.397059 0.411765 0.426471 0.441176 0.455882 0.470588 0.485294 0.5 0.514706 0.529412 0.544118 0.558824 0.573529 0.588235 0.602941 0.617647 0.632353 0.647059 0.661765 0.676471 0.691176 0.705882 0.720588 0.735294 0.75 0.764706 0.779412 0.794118 0.808824 0.823529 0.838235 0.852941 0.867647 0.882353 0.897059 0.911765 0.926471 0.941176 0.955882 0.970588 0.985294 1 1 1 1 1
  line L1 (9.6, 75.0055) -> (9.6, 73.5055)
  line L2 (-21.667, 0) -> (193.4278, 0) projected
  point P0 (12.5882, 74.0529)
  point P1 (15.5765, 74.6595)
  point P2 (18.5647, 75.3157)
  point P3 (21.5529, 76.0122)
  point P4 (24.5412, 76.7397)
  point P5 (27.5294, 77.4888)
  point P6 (30.5176, 78.2499)
  point P7 (33.5059, 79.0139)
  point P8 (36.4941, 79.7712)
  point P9 (39.4824, 80.5126)
  point P10 (42.4706, 81.2285)
  point P11 (45.4588, 81.9096)
  point P12 (48.4471, 82.5466)
  point P13 (51.4353, 83.1361)
  point P14 (54.4235, 83.7124)
  point P15 (57.4118, 84.2824)
  point P16 (57.4118, 85.7824)
  point P17 (54.4235, 85.2124)
  point P18 (51.4353, 84.6361)
  point P19 (48.4471, 84.0466)
  point P20 (45.4588, 83.4096)
  point P21 (42.4706, 82.7285)
  point P22 (39.4824, 82.0126)
  point P23 (36.4941, 81.2712)
  point P24 (33.5059, 80.5139)
  point P25 (30.5176, 79.7499)
  point P26 (27.5294, 78.9888)
  point P27 (24.5412, 78.2397)
  point P28 (21.5529, 77.5122)
  point P29 (18.5647, 76.8157)
  point P30 (15.5765, 76.1595)
  point P31 (12.5882, 75.5529)
  constraints: 4 end point, 36 other
revolve "Velcro_closure_thigh_near_v8" add sketch "S8_vel_thigh_near" angle 51.973 mid plane about axis through (0, -10, 0) along (0, 1, 0) separate body
ref_plane "Work Plane10" through (0, 0, 0) normal (-0.2561526, 0, 0.9666364) x (0, 1, 0)
sketch "S8_vel_shank_near" plane through (0, 0, 0) normal (-0.2561526, 0, 0.9666364) x (0, 1, 0)
  spline S0 degree 4 poles (-60.4, 68.8155) (-60.2132, 68.8227) (-59.8395, 68.8372) (-59.279, 68.859) (-58.5317, 68.8882) (-57.7844, 68.9177) (-57.0371, 68.9474) (-56.2898, 68.9773) (-55.5426, 69.0075) (-54.7953, 69.0379) (-54.048, 69.0686) (-53.3007, 69.0995) (-52.5535, 69.1307) (-51.8062, 69.1621) (-51.0589, 69.1938) (-50.3117, 69.2258) (-49.5644, 69.258) (-48.8172, 69.2906) (-48.07, 69.3234) (-47.3227, 69.3565) (-46.5755, 69.3899) (-45.8283, 69.4236) (-45.0811, 69.4576) (-44.3339, 69.4919) (-43.5867, 69.5265) (-42.8395, 69.5615) (-42.0923, 69.5967) (-41.3452, 69.6323) (-40.598, 69.6682) (-39.8508, 69.7045) (-39.1037, 69.7411) (-38.3565, 69.7781) (-37.6094, 69.8154) (-36.8623, 69.8531) (-36.1152, 69.8911) (-35.3681, 69.9295) (-34.621, 69.9682) (-33.8739, 70.0074) (-33.1268, 70.0469) (-32.3797, 70.0868) (-31.6327, 70.1271) (-30.8856, 70.1678) (-30.1386, 70.2089) (-29.3915, 70.2504) (-28.6445, 70.2923) (-27.8975, 70.3346) (-27.1505, 70.3774) (-26.4035, 70.4205) (-25.6566, 70.4641) (-24.9096, 70.5081) (-24.1626, 70.5526) (-23.4157, 70.5975) (-22.6688, 70.6429) (-21.9219, 70.6887) (-21.175, 70.7349) (-20.4281, 70.7817) (-19.6812, 70.8289) (-18.9344, 70.8765) (-18.1875, 70.9247) (-17.4407, 70.9733) (-16.6939, 71.0224) (-15.9471, 71.072) (-15.2003, 71.1221) (-14.4536, 71.1727) (-13.7068, 71.2237) (-12.9601, 71.2754) (-12.2134, 71.3275) (-11.4667, 71.3801) (-10.72, 71.4333) (-10.16, 71.4735) (-9.7867, 71.5006) (-9.6, 71.5141) knots 0 0 0 0 0 0.014706 0.029412 0.044118 0.058824 0.073529 0.088235 0.102941 0.117647 0.132353 0.147059 0.161765 0.176471 0.191176 0.205882 0.220588 0.235294 0.25 0.264706 0.279412 0.294118 0.308824 0.323529 0.338235 0.352941 0.367647 0.382353 0.397059 0.411765 0.426471 0.441176 0.455882 0.470588 0.485294 0.5 0.514706 0.529412 0.544118 0.558824 0.573529 0.588235 0.602941 0.617647 0.632353 0.647059 0.661765 0.676471 0.691176 0.705882 0.720588 0.735294 0.75 0.764706 0.779412 0.794118 0.808824 0.823529 0.838235 0.852941 0.867647 0.882353 0.897059 0.911765 0.926471 0.941176 0.955882 0.970588 0.985294 1 1 1 1 1
  line L0 (-9.6, 71.5141) -> (-9.6, 73.0141)
  spline S1 degree 4 poles (-9.6, 73.0141) (-9.7867, 73.0006) (-10.16, 72.9735) (-10.72, 72.9333) (-11.4667, 72.8801) (-12.2134, 72.8275) (-12.9601, 72.7754) (-13.7068, 72.7237) (-14.4536, 72.6727) (-15.2003, 72.6221) (-15.9471, 72.572) (-16.6939, 72.5224) (-17.4407, 72.4733) (-18.1875, 72.4247) (-18.9344, 72.3765) (-19.6812, 72.3288) (-20.4281, 72.2817) (-21.175, 72.2349) (-21.9219, 72.1887) (-22.6688, 72.1429) (-23.4157, 72.0975) (-24.1626, 72.0526) (-24.9096, 72.0081) (-25.6566, 71.9641) (-26.4035, 71.9205) (-27.1505, 71.8774) (-27.8975, 71.8346) (-28.6445, 71.7923) (-29.3915, 71.7504) (-30.1386, 71.7089) (-30.8856, 71.6678) (-31.6327, 71.6271) (-32.3797, 71.5868) (-33.1268, 71.5469) (-33.8739, 71.5074) (-34.621, 71.4682) (-35.3681, 71.4295) (-36.1152, 71.3911) (-36.8623, 71.353) (-37.6094, 71.3154) (-38.3565, 71.2781) (-39.1037, 71.2411) (-39.8508, 71.2045) (-40.598, 71.1682) (-41.3452, 71.1323) (-42.0923, 71.0967) (-42.8395, 71.0615) (-43.5867, 71.0265) (-44.3339, 70.9919) (-45.0811, 70.9576) (-45.8283, 70.9236) (-46.5755, 70.8899) (-47.3227, 70.8565) (-48.07, 70.8234) (-48.8172, 70.7906) (-49.5644, 70.758) (-50.3117, 70.7258) (-51.0589, 70.6938) (-51.8062, 70.6621) (-52.5535, 70.6307) (-53.3007, 70.5995) (-54.048, 70.5686) (-54.7953, 70.5379) (-55.5426, 70.5075) (-56.2898, 70.4773) (-57.0371, 70.4474) (-57.7844, 70.4177) (-58.5317, 70.3882) (-59.279, 70.359) (-59.8395, 70.3372) (-60.2132, 70.3227) (-60.4, 70.3155) knots 0 0 0 0 0 0.014706 0.029412 0.044118 0.058824 0.073529 0.088235 0.102941 0.117647 0.132353 0.147059 0.161765 0.176471 0.191176 0.205882 0.220588 0.235294 0.25 0.264706 0.279412 0.294118 0.308824 0.323529 0.338235 0.352941 0.367647 0.382353 0.397059 0.411765 0.426471 0.441176 0.455882 0.470588 0.485294 0.5 0.514706 0.529412 0.544118 0.558824 0.573529 0.588235 0.602941 0.617647 0.632353 0.647059 0.661765 0.676471 0.691176 0.705882 0.720588 0.735294 0.75 0.764706 0.779412 0.794118 0.808824 0.823529 0.838235 0.852941 0.867647 0.882353 0.897059 0.911765 0.926471 0.941176 0.955882 0.970588 0.985294 1 1 1 1 1
  line L1 (-60.4, 70.3155) -> (-60.4, 68.8155)
  line L2 (-105.6308, 0) -> (207.4218, 0) projected
  point P0 (-57.4118, 68.9325)
  point P1 (-54.4235, 69.0532)
  point P2 (-51.4353, 69.1779)
  point P3 (-48.4471, 69.3068)
  point P4 (-45.4588, 69.4404)
  point P5 (-42.4706, 69.5789)
  point P6 (-39.4824, 69.7226)
  point P7 (-36.4941, 69.8718)
  point P8 (-33.5059, 70.0269)
  point P9 (-30.5176, 70.1881)
  point P10 (-27.5294, 70.3557)
  point P11 (-24.5412, 70.5301)
  point P12 (-21.5529, 70.7116)
  point P13 (-18.5647, 70.9004)
  point P14 (-15.5765, 71.0969)
  point P15 (-12.5882, 71.3014)
  point P16 (-12.5882, 72.8014)
  point P17 (-15.5765, 72.5969)
  point P18 (-18.5647, 72.4004)
  point P19 (-21.5529, 72.2116)
  point P20 (-24.5412, 72.0301)
  point P21 (-27.5294, 71.8557)
  point P22 (-30.5176, 71.6881)
  point P23 (-33.5059, 71.5269)
  point P24 (-36.4941, 71.3718)
  point P25 (-39.4824, 71.2226)
  point P26 (-42.4706, 71.0789)
  point P27 (-45.4588, 70.9404)
  point P28 (-48.4471, 70.8068)
  point P29 (-51.4353, 70.6779)
  point P30 (-54.4235, 70.5532)
  point P31 (-57.4118, 70.4325)
  constraints: 4 end point, 36 other
revolve "Velcro_closure_shank_near_v8" add sketch "S8_vel_shank_near" angle 58.993 mid plane about axis through (0, -10, 0) along (0, 1, 0) separate body
ref_plane "Work Plane11" through (0, 0, 0) normal (-0.3123949, 0, 0.9499523) x (0, 1, 0)
sketch "S8_vel_shank_far" plane through (0, 0, 0) normal (-0.3123949, 0, 0.9499523) x (0, 1, 0)
  spline S0 degree 4 poles (-132.7, 66.3365) (-132.5236, 66.3425) (-132.1708, 66.3544) (-131.6416, 66.3724) (-130.9361, 66.3964) (-130.2305, 66.4206) (-129.525, 66.4448) (-128.8194, 66.4692) (-128.1138, 66.4936) (-127.4083, 66.5182) (-126.7027, 66.5428) (-125.9972, 66.5676) (-125.2916, 66.5925) (-124.5861, 66.6174) (-123.8805, 66.6425) (-123.175, 66.6677) (-122.4694, 66.693) (-121.7639, 66.7184) (-121.0583, 66.7439) (-120.3528, 66.7696) (-119.6473, 66.7952) (-118.9417, 66.8208) (-118.2362, 66.8463) (-117.5306, 66.8716) (-116.8251, 66.8968) (-116.1195, 66.9217) (-115.414, 66.9466) (-114.7084, 66.9714) (-114.0029, 66.996) (-113.2973, 67.0205) (-112.5917, 67.0449) (-111.8862, 67.0692) (-111.1806, 67.0934) (-110.4751, 67.1175) (-109.7695, 67.1415) (-109.0639, 67.1653) (-108.3584, 67.1891) (-107.8292, 67.2069) (-107.4764, 67.2187) (-107.3, 67.2247) knots 0 0 0 0 0 0.027778 0.055556 0.083333 0.111111 0.138889 0.166667 0.194444 0.222222 0.25 0.277778 0.305556 0.333333 0.361111 0.388889 0.416667 0.444444 0.472222 0.5 0.527778 0.555556 0.583333 0.611111 0.638889 0.666667 0.694444 0.722222 0.75 0.777778 0.805556 0.833333 0.861111 0.888889 0.916667 0.944444 0.972222 1 1 1 1 1
  line L0 (-107.3, 67.2247) -> (-107.3, 68.7247)
  spline S1 degree 4 poles (-107.3, 68.7247) (-107.4764, 68.7187) (-107.8292, 68.7069) (-108.3584, 68.6891) (-109.0639, 68.6653) (-109.7695, 68.6415) (-110.4751, 68.6175) (-111.1806, 68.5934) (-111.8862, 68.5692) (-112.5917, 68.5449) (-113.2973, 68.5205) (-114.0029, 68.496) (-114.7084, 68.4714) (-115.414, 68.4466) (-116.1195, 68.4217) (-116.8251, 68.3968) (-117.5306, 68.3716) (-118.2362, 68.3463) (-118.9417, 68.3208) (-119.6473, 68.2952) (-120.3528, 68.2696) (-121.0583, 68.2439) (-121.7639, 68.2184) (-122.4694, 68.193) (-123.175, 68.1677) (-123.8805, 68.1425) (-124.5861, 68.1174) (-125.2916, 68.0925) (-125.9972, 68.0676) (-126.7027, 68.0428) (-127.4083, 68.0182) (-128.1138, 67.9936) (-128.8194, 67.9692) (-129.525, 67.9448) (-130.2305, 67.9206) (-130.9361, 67.8964) (-131.6416, 67.8724) (-132.1708, 67.8544) (-132.5236, 67.8425) (-132.7, 67.8365) knots 0 0 0 0 0 0.027778 0.055556 0.083333 0.111111 0.138889 0.166667 0.194444 0.222222 0.25 0.277778 0.305556 0.333333 0.361111 0.388889 0.416667 0.444444 0.472222 0.5 0.527778 0.555556 0.583333 0.611111 0.638889 0.666667 0.694444 0.722222 0.75 0.777778 0.805556 0.833333 0.861111 0.888889 0.916667 0.944444 0.972222 1 1 1 1 1
  line L1 (-132.7, 67.8365) -> (-132.7, 66.3365)
  line L2 (-192.0848, 0) -> (221.8308, 0) projected
  point P0 (-129.8778, 66.4327)
  point P1 (-127.0556, 66.5305)
  point P2 (-124.2333, 66.63)
  point P3 (-121.4111, 66.7312)
  point P4 (-118.5889, 66.8336)
  point P5 (-115.7667, 66.9342)
  point P6 (-112.9444, 67.0327)
  point P7 (-110.1222, 67.1295)
  point P8 (-110.1222, 68.6295)
  point P9 (-112.9444, 68.5327)
  point P10 (-115.7667, 68.4342)
  point P11 (-118.5889, 68.3336)
  point P12 (-121.4111, 68.2312)
  point P13 (-124.2333, 68.13)
  point P14 (-127.0556, 68.0305)
  point P15 (-129.8778, 67.9327)
  constraints: 4 end point, 20 other
revolve "Velcro_closure_shank_far_v8" add sketch "S8_vel_shank_far" angle 61.791 mid plane about axis through (0, -10, 0) along (0, 1, 0) separate body
ref_plane "Work Plane12" through (0, 0, 0) normal (0, 0, -1) x (0, 1, 0)
sketch "S8_m3_1" plane through (0, 0, 0) normal (0, 0, -1) x (0, 1, 0)
  spline S0 degree 4 poles (95, 97.0075) (95.1562, 97.0343) (95.4686, 97.0878) (95.9371, 97.168) (96.5619, 97.2749) (97.1866, 97.3817) (97.8114, 97.4884) (98.4361, 97.595) (99.0609, 97.7014) (99.6857, 97.8078) (100.3105, 97.9139) (100.9353, 98.0198) (101.5602, 98.1256) (102.185, 98.231) (102.8099, 98.3363) (103.4348, 98.4412) (104.0597, 98.5459) (104.6846, 98.6503) (105.3096, 98.7545) (105.9345, 98.8584) (106.5595, 98.9622) (107.1845, 99.0657) (107.8095, 99.169) (108.4346, 99.2721) (109.0596, 99.3749) (109.6847, 99.4776) (110.3098, 99.5801) (110.9348, 99.6823) (111.5599, 99.7844) (112.1851, 99.8863) (112.8102, 99.9881) (113.4353, 100.0896) (114.0605, 100.191) (114.6857, 100.2922) (115.3108, 100.3932) (115.936, 100.4941) (116.5612, 100.5949) (117.1864, 100.6955) (117.8117, 100.796) (118.4369, 100.8963) (119.0621, 100.9965) (119.5311, 101.0716) (119.8437, 101.1216) (120, 101.1466) knots 0 0 0 0 0 0.025 0.05 0.075 0.1 0.125 0.15 0.175 0.2 0.225 0.25 0.275 0.3 0.325 0.35 0.375 0.4 0.425 0.45 0.475 0.5 0.525 0.55 0.575 0.6 0.625 0.65 0.675 0.7 0.725 0.75 0.775 0.8 0.825 0.85 0.875 0.9 0.925 0.95 0.975 1 1 1 1 1
  line L0 (120, 101.1466) -> (120, 102.6466)
  spline S1 degree 4 poles (120, 102.6466) (119.8437, 102.6216) (119.5311, 102.5716) (119.0621, 102.4965) (118.4369, 102.3963) (117.8117, 102.296) (117.1864, 102.1955) (116.5612, 102.0949) (115.936, 101.9941) (115.3108, 101.8933) (114.6857, 101.7922) (114.0605, 101.691) (113.4353, 101.5896) (112.8102, 101.4881) (112.1851, 101.3863) (111.5599, 101.2844) (110.9348, 101.1823) (110.3098, 101.0801) (109.6847, 100.9776) (109.0596, 100.8749) (108.4346, 100.7721) (107.8095, 100.669) (107.1845, 100.5657) (106.5595, 100.4622) (105.9345, 100.3584) (105.3096, 100.2545) (104.6846, 100.1503) (104.0597, 100.0459) (103.4348, 99.9412) (102.8099, 99.8363) (102.185, 99.7311) (101.5602, 99.6256) (100.9353, 99.5199) (100.3105, 99.4139) (99.6857, 99.3078) (99.0609, 99.2014) (98.4361, 99.095) (97.8114, 98.9884) (97.1866, 98.8817) (96.5619, 98.7749) (95.9371, 98.668) (95.4686, 98.5878) (95.1562, 98.5343) (95, 98.5075) knots 0 0 0 0 0 0.025 0.05 0.075 0.1 0.125 0.15 0.175 0.2 0.225 0.25 0.275 0.3 0.325 0.35 0.375 0.4 0.425 0.45 0.475 0.5 0.525 0.55 0.575 0.6 0.625 0.65 0.675 0.7 0.725 0.75 0.775 0.8 0.825 0.85 0.875 0.9 0.925 0.95 0.975 1 1 1 1 1
  line L1 (95, 98.5075) -> (95, 97.0075)
  line L2 (-191.78, 0) -> (221.78, 0) projected
  point P0 (97.5, 97.4352)
  point P1 (100, 97.8611)
  point P2 (102.5, 98.2841)
  point P3 (105, 98.7028)
  point P4 (107.5, 99.1178)
  point P5 (110, 99.5293)
  point P6 (112.5, 99.9376)
  point P7 (115, 100.343)
  point P8 (117.5, 100.7459)
  point P9 (117.5, 102.2459)
  point P10 (115, 101.843)
  point P11 (112.5, 101.4376)
  point P12 (110, 101.0293)
  point P13 (107.5, 100.6178)
  point P14 (105, 100.2028)
  point P15 (102.5, 99.7841)
  point P16 (100, 99.3611)
  point P17 (97.5, 98.9352)
  dimension "d7" = 105
  dimension "d8" = 105
  dimension "d11" = 95.5
  dimension "d14" = 50
  dimension "d17" = 48.5
  constraints: 4 end point, 22 other
revolve "M3_patch_thigh_v8" add sketch "S8_m3_1" angle 23.122 mid plane about axis through (0, -10, 0) along (0, 1, 0) separate body
ref_plane "Work Plane13" through (0, 0, 0) normal (0, 0, -1) x (0, 1, 0)